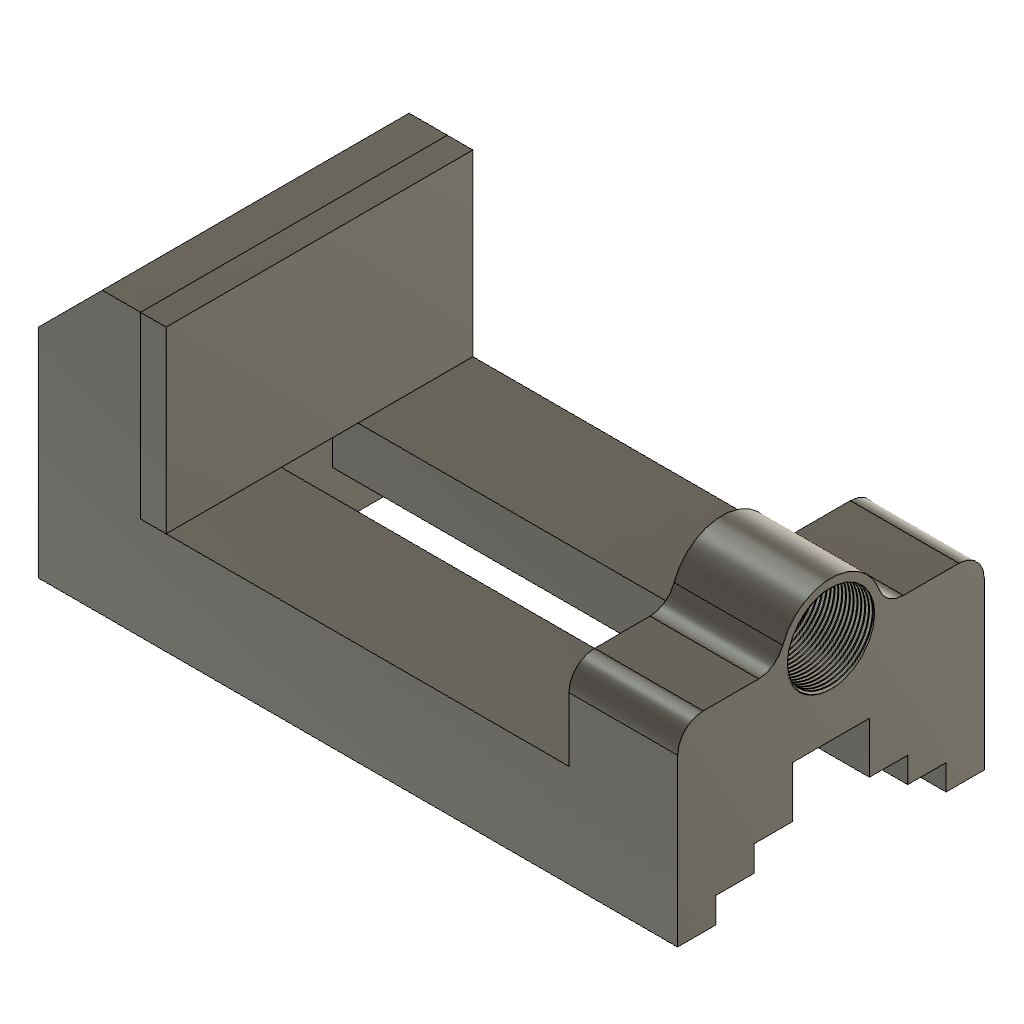
body+1 (Autodesk Fusion 360 archive; units mm, degrees)
design "body 1"
part number: 2026-10-02-19-15-55-777
part number: 2026-10-07-14-51-14-038
part number: 2026-10-07-14-51-19-169
Autodesk Fusion 360 part; units mm, degrees
sketch "Sketch1" plane through (0, 0, 0) normal (0, 0, 1) x (1, 0, 0)
  line L0 (125, 60) -> (-125, 60)
  line L1 (-125, 60) -> (-125, -60)
  line L2 (-125, -60) -> (125, -60)
  line L3 (125, -60) -> (125, 60)
  line L4 (125, 60) -> (-125, -60) construction
  line L5 (-125, 60) -> (125, -60) construction
  line L6 (-50, 60) -> (60, 60)
  dimension "d1" = 250
  dimension "d2" = 120
  constraint horizontal L0
  constraint perpendicular L0 L1
  constraint parallel L0 L2
  constraint parallel L1 L3
  constraint coincident L4 origin
  constraint coincident L5 origin
  constraint horizontal L6
  constraint coincident L0 L6.start
  measures "d1" distance of L1.end L2.end
  measures "d2" distance of L0.end L1.end
extrude "Extrude3" add sketch "Sketch1" along normal blind 110 makes body 1
sketch "Sketch4" plane through (0, 0, 110) normal (0, 0, 1) x (-1, 0, 0)
  line L0 (125, -60) -> (125, 60)
  line L1 (125, 60) -> (-125, 60)
  line L2 (-125, 60) -> (-125, -60)
  line L3 (-125, -60) -> (125, -60)
  line L4 (85, -60) -> (85, 60)
  line L5 (-82.5, -60) -> (-82.5, 60)
  dimension "d19" = 40
  dimension "d20" = 167.5
  constraint coincident L3 L4.start
  constraint coincident L1 L4.end
  constraint perpendicular L1 L4
  constraint coincident L3 L5.start
  constraint coincident L1 L5.end
  constraint perpendicular L1 L5
  measures "d19" distance of L0 L4
  measures "d20" distance of L4 L5
extrude "Extrude4" cut sketch "Sketch4" against normal blind 70 contours L1 L3 L4 L5 bodies 1
sketch "Sketch6" plane through (125, 0, 0) normal (1, 0, 0) x (0, 1, 0)
  line L0 (-60, 0) -> (60, 0)
  line L1 (60, 0) -> (60, 110)
  line L2 (60, 110) -> (-60, 110)
  line L3 (-60, 110) -> (-60, 0)
  line L4 (-60, 75) -> (60, 75)
  circle A0 centre (0, 75) radius 20
  circle A1 centre (0, 75) radius 15
  line L5 (-45, 0) -> (-45, 10)
  line L6 (-30, 10) -> (-30, 20)
  line L7 (-15, 20) -> (-15, 40)
  line L8 (-45, 10) -> (-30, 10)
  line L9 (-30, 20) -> (-15, 20)
  line L10 (-15, 40) -> (0.0005, 40)
  line L11 (45, 0) -> (45, 10)
  line L12 (45, 10) -> (30, 10)
  line L13 (30, 20) -> (15, 20)
  line L14 (30, 10) -> (30, 20)
  line L15 (15, 20) -> (15, 40)
  line L16 (0.0005, 40) -> (15, 40)
  point P0 (60, 0)
  dimension "d26" = 75
  dimension "d27" = 40
  dimension "d29" = -5
  dimension "d30" = 10
  dimension "d32" = 10
  dimension "d34" = 20
  dimension "d56" = 40
  dimension "d57" = 45
  dimension "d58" = 30
  dimension "d59" = 15
  constraint coincident L3 L4.start
  constraint coincident L1 L4.end
  constraint perpendicular L1 L4
  constraint midpoint L4 A0.centre
  constraint coincident L0 L5.start
  constraint perpendicular L0 L5
  constraint vertical L6
  constraint vertical L7
  constraint perpendicular L6 L8
  measures "d26" distance of L0 L4
  measures "d27" diameter of A0
  measures "d30" distance of L5.start L5.end
  measures "d32" distance of L6.start L6.end
  measures "d34" distance of L7.start L7.end
  measures "d56" distance of L0 L10
  measures "d57" distance of L3 L7
  measures "d58" distance of L3 L6
  measures "d59" distance of L3 L5
extrude "Extrude5" cut sketch "Sketch6" against normal blind 90 contours L1 L2 L3 L4 A0 bodies 1
extrude "Extrude6" cut sketch "Sketch6" against normal blind 210 contours L0 L5 L6 L7 L8 L9 L10 L11 L12 L13 L14 L15 L16 | L4 A1 | L4 A1 bodies 1
fillet "Fillet1" radius 10 1 edges at (103.75, -60, 75) on bodies 1
fillet "Fillet2" radius 10 1 edges at (103.75, -20, 75) on bodies 1
fillet "Fillet3" radius 10 1 edges at (103.75, 20, 75) on bodies 1
fillet "Fillet4" radius 10 1 edges at (103.75, 60, 75) on bodies 1
sketch "Sketch7" plane through (0, 0, 40) normal (0, 0, 1) x (-1, 0, 0)
  line L0 (85, -60) -> (85, -15)
  line L1 (85, 60) -> (-82.5, 60)
  line L2 (-82.5, -15) -> (-82.5, -60)
  line L3 (-82.5, -60) -> (85, -60)
  line L4 (-40, -59) -> (-40, 59)
  line L5 (-40, 59) -> (-82.5, 59)
  line L6 (-40, -59) -> (-82.5, -59)
  line L7 (-82.5, 15) -> (85, 15)
  line L8 (85, 15) -> (85, 60)
  line L9 (85, -15) -> (-82.5, -15)
  line L10 (-82.5, 60) -> (-82.5, 15)
  dimension "d50" = 118
  dimension "d51" = 42.5
  dimension "d52" = 1
  constraint vertical L4
  constraint coincident L2 L5.end
  constraint perpendicular L2 L5
  constraint coincident L2 L6.end
  constraint perpendicular L2 L6
  measures "d50" distance of L4.start L4.end
  measures "d51" distance of L2 L4
  measures "d52" distance of L3 L4.start
chamfer "Chamfer2" distance 25 angle 45 1 edges at (-125, 0, 110) tangent chain off on bodies 1
thread "Thread1" "ISO Metric profile 35.0 M35x1.5 M35x1.5 6H" major diameter 35.208 minor diameter 33.526 pitch 1.5 angle 60 modelled right hand crest width 0.4036 on face at (110.8333, 14.9255, 76.4935) crest through (124.625, 16.763, 75) on bodies 1
sketch "Sketch8" plane through (-85, 0, 0) normal (1, 0, 0) x (0, 1, 0)
  line L0 (60, 110) -> (-60, 110)
  line L1 (-60, 110) -> (-60, 40)
  line L2 (-60, 40) -> (-15, 40)
  line L3 (-15, 40) -> (-15, 20)
  line L4 (-15, 20) -> (-30, 20)
  line L5 (-30, 20) -> (-30, 10)
  line L6 (-30, 10) -> (-45, 10)
  line L7 (-45, 10) -> (-45, 0)
  line L8 (-45, 0) -> (45, 0)
  line L9 (45, 0) -> (45, 10)
  line L10 (45, 10) -> (30, 10)
  line L11 (30, 10) -> (30, 20)
  line L12 (30, 20) -> (15, 20)
  line L13 (15, 20) -> (15, 40)
  line L14 (15, 40) -> (60, 40)
  line L15 (60, 40) -> (60, 110)
  line L16 (-60, 110) -> (60, 110)
  line L17 (60, 110) -> (60, 40)
  line L18 (60, 40) -> (-60, 40)
  line L19 (-60, 40) -> (-60, 110)
  constraint horizontal L16
  constraint vertical L17
  constraint horizontal L18
  constraint vertical L19
  constraint coincident L14.end L15.start
  constraint coincident L0.end L1.start
extrude "Extrude8" add sketch "Sketch8" along normal blind 10 separate body contours L0 L1 L2 L14 L15 L16 L17 L18 L19 makes body 2
copy_body "Body->Comp1" bodies 2 removing the originals makes body 3 in component "rect"
copy_body "Body->Comp2" bodies 1 removing the originals makes body 4 in component "base"
component "rect" placed x (1, 0, 0) y (0, 1, 0) z (0, 0, 1) at (0, 0, 0)
component "base" placed x (1, 0, 0) y (0, 1, 0) z (0, 0, 1) at (0, 0, 0)
equation "d20 = 125 mm + 42.5 mm"
named bodies: "base", "rect"
